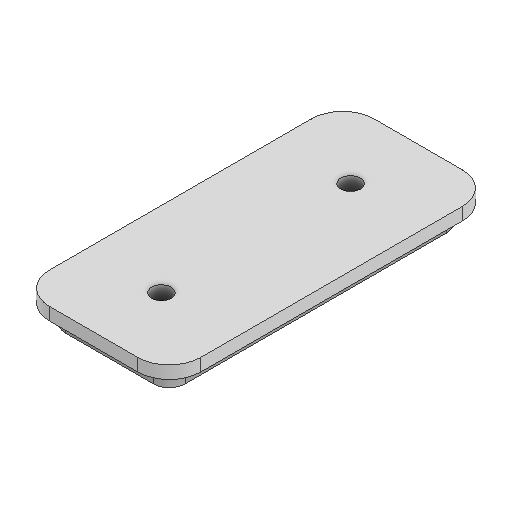
# Autodesk Inventor part: 3DP_PLA_Antenna_Boom_Log_Periodic_Clamp_REVB
Saved by Autodesk Inventor 2027 (Build 310192060, 192F)
## iProperties
Created: 2026-07-04
Part Number: 3DP_PLA_Antenna_Boom_Log_Periodic_Clamp_REVB
Material: Generic
Document SubType Name: Modeling
Designer: lacze
Density: 1 g/cm^3
Appearance: Default
Author: lacze
Autodesk Inventor part; units mm, degrees
ref_plane "YZ Plane" through (0, 0, 0) normal (1, 0, 0) x (0, 1, 0)
ref_plane "XZ Plane" through (0, 0, 0) normal (0, 1, 0) x (-1, 0, 0)
ref_plane "XY Plane" through (0, 0, 0) normal (0, 0, 1) x (1, 0, 0)
sketch "Sketch1" plane through (0, 0, 0) normal (0, 1, 0) x (-1, 0, 0)
  line L0 (20, 47.5) -> (-20, 47.5)
  line L1 (-20, 47.5) -> (-20, -47.5)
  line L2 (-20, -47.5) -> (20, -47.5)
  line L3 (20, -47.5) -> (20, 47.5)
  line L4 (-19, 46.5) -> (19, 46.5)
  line L5 (19, 46.5) -> (19, -46.5)
  line L6 (19, -46.5) -> (-19, -46.5)
  line L7 (-19, -46.5) -> (-19, 46.5)
  point P0 (0, 0)
  point P1 (0, 30)
  point P2 (0, -30)
  dimension "d0" = 40
  dimension "d1" = 95
  dimension "d2" = 20
  dimension "d3" = 47.5
  dimension "d4" = 20
  dimension "d5" = 20
  dimension "d6" = 17.5
  dimension "d7" = 17.5
  dimension "d8" = 1
  constraints: 16 end point, 4 parallel, 2 perpendicular, 1 horizontal, 3 other
  measures "d0" distance of L2.end L1.end
  measures "d1" distance of L1.end L0.end
  measures "d2" distance from line of point (0, 0) L3
  measures "d3" distance from line of L0 point (0, 0)
  measures "d4" distance from line of L3 point (0, 30)
  measures "d5" distance from line of L3 point (0, -30)
  measures "d6" distance from line of L0 point (0, 30)
  measures "d7" distance from line of L2 point (0, -30)
  measures "d8" distance between parallel lines of L0 L4
extrude "Extrusion1" add sketch "Sketch1" along normal blind 5.8 contours L4 L5 L6 L7
fillet "Fillet1" radius 5 4 edges at (19, 2.9, 46.5) (-19, 2.9, 46.5) (19, 2.9, -46.5) (-19, 2.9, -46.5)
hole "Hole1" at (0, 0, 30) at (0, 0, -30) direction (0, 1, 0) diameter 6.2 end through all
sketch "Sketch2" plane through (0, 5.8, 0) normal (0, 1, 0) x (1, 0, 0)
  circle A0 centre (0, 30) radius 3.1 projected
  circle A1 centre (0, -30) radius 3.1 projected
  arc A2 (-14, 46.5) -> (-19, 41.5) centre (-14, 41.5) ccw projected
  line L0 (-19, 41.5) -> (-19, -41.5) projected
  arc A3 (-19, -41.5) -> (-14, -46.5) centre (-14, -41.5) ccw projected
  line L1 (-14, -46.5) -> (14, -46.5) projected
  arc A4 (14, -46.5) -> (19, -41.5) centre (14, -41.5) ccw projected
  line L2 (19, -41.5) -> (19, 41.5) projected
  arc A5 (19, 41.5) -> (14, 46.5) centre (14, 41.5) ccw projected
  line L3 (14, 46.5) -> (-14, 46.5) projected
  line L4 (-24, -41.5) -> (-24, 41.5)
  arc A6 (-14, 51.5) -> (-24, 41.5) centre (-14, 41.5) ccw
  line L5 (-14, 51.5) -> (14, 51.5)
  arc A7 (24, 41.5) -> (14, 51.5) centre (14, 41.5) ccw
  line L6 (24, 41.5) -> (24, -41.5)
  arc A8 (14, -51.5) -> (24, -41.5) centre (14, -41.5) ccw
  line L7 (14, -51.5) -> (-14, -51.5)
  arc A9 (-24, -41.5) -> (-14, -51.5) centre (-14, -41.5) ccw
  point P0 (0, 0)
  dimension "d19" = 5
  constraints: 8 end point, 8 point on circle, 4 centre point, 7 other
  measures "d19" distance between parallel lines of L0 L4
extrude "Extrusion2" add sketch "Sketch2" along normal blind 4 contours L3 A5 L2 A4 L1 A3 L0 A2 | L4 A6 L5 A7 L6 A8 L7 A9
equation "\"d2\" = 0.5 * d0"
equation "\"d3\" = 0.5 * d1"
body "Solid1"
